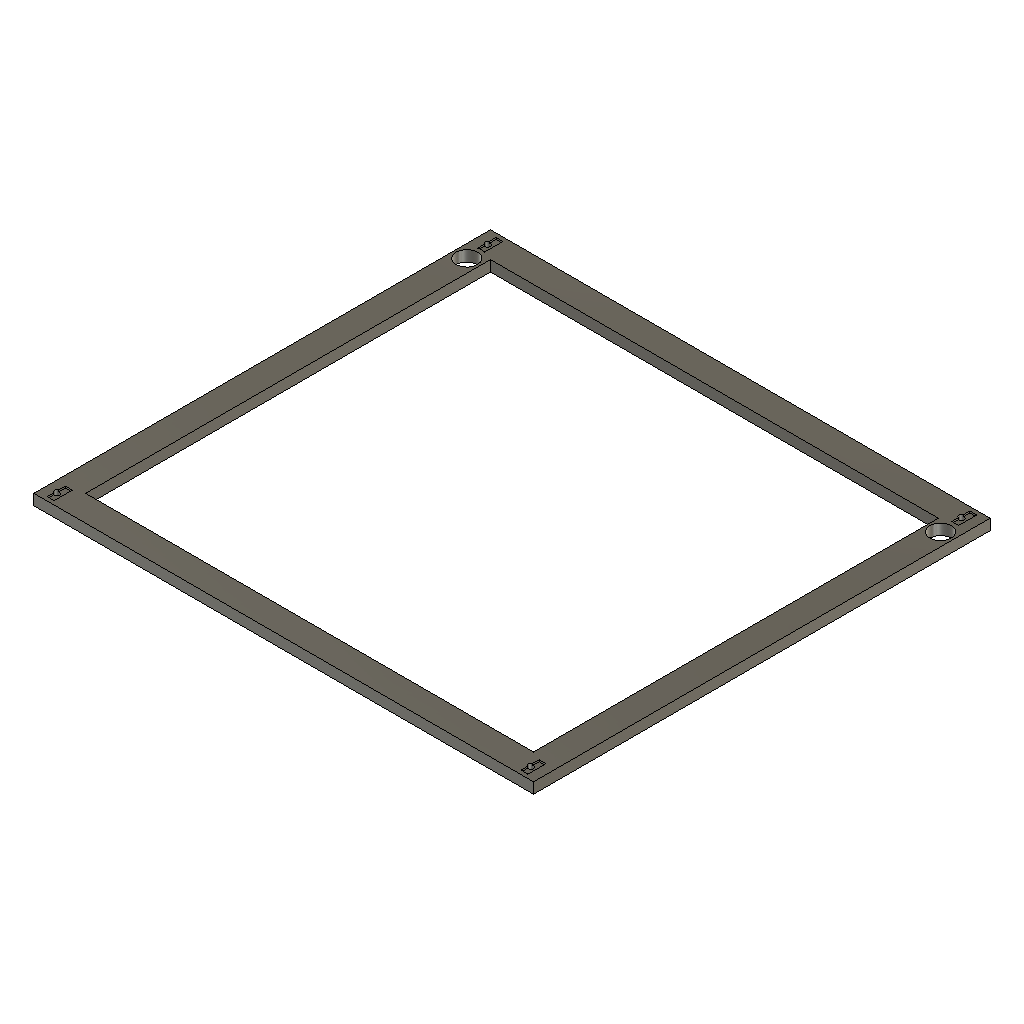
carrier-jig-240 (Autodesk Fusion 360 design; units mm, degrees)
part number: 2026-10-31-09-47-41-817
part number: 2026-10-31-09-47-42-158
Autodesk Fusion 360 part; units mm, degrees
sketch "Left spine sketch" plane through (0, 0, 0) normal (0, 0, 1) x (1, 0, 0) in component "PRINT alignment jig"
  line L0 (4, 14) -> (16, 14)
  line L1 (16, 14) -> (16, 226)
  line L2 (16, 226) -> (4, 226)
  line L3 (4, 226) -> (4, 14)
  dimension "d67" = 4
  dimension "d68" = 14
  dimension "d69" = 12
  dimension "d70" = 212
  constraint horizontal L0
  constraint vertical L1
  constraint horizontal L2
  constraint vertical L3
  measures "d67" horizontal distance of origin L0.start
  measures "d68" vertical distance of origin L0.start
  measures "d69" horizontal distance of L0.start L0.end
  measures "d70" vertical distance of L0.end L1.end
extrude "Left spine" add sketch "Left spine sketch" along normal blind 5 in component "PRINT alignment jig"
sketch "Bottom bridge sketch" plane through (0, 0, 0) normal (0, 0, 1) x (1, 0, 0) in component "PRINT alignment jig"
  line L0 (4, 14) -> (236, 14)
  line L1 (236, 14) -> (236, 26)
  line L2 (236, 26) -> (4, 26)
  line L3 (4, 26) -> (4, 14)
  dimension "d73" = 4
  dimension "d74" = 14
  dimension "d75" = 232
  dimension "d76" = 12
  constraint horizontal L0
  constraint vertical L1
  constraint horizontal L2
  constraint vertical L3
  measures "d73" horizontal distance of origin L0.start
  measures "d74" vertical distance of origin L0.start
  measures "d75" horizontal distance of L0.start L0.end
  measures "d76" vertical distance of L0.end L1.end
extrude "Bottom bridge" add sketch "Bottom bridge sketch" along normal blind 5 in component "PRINT alignment jig"
sketch "Right spine sketch" plane through (0, 0, 0) normal (0, 0, 1) x (1, 0, 0) in component "PRINT alignment jig"
  line L0 (224, 14) -> (236, 14)
  line L1 (236, 14) -> (236, 226)
  line L2 (236, 226) -> (224, 226)
  line L3 (224, 226) -> (224, 14)
  dimension "d79" = 224
  dimension "d80" = 14
  dimension "d81" = 12
  dimension "d82" = 212
  constraint horizontal L0
  constraint vertical L1
  constraint horizontal L2
  constraint vertical L3
  measures "d79" horizontal distance of origin L0.start
  measures "d80" vertical distance of origin L0.start
  measures "d81" horizontal distance of L0.start L0.end
  measures "d82" vertical distance of L0.end L1.end
extrude "Right spine" add sketch "Right spine sketch" along normal blind 5 in component "PRINT alignment jig"
sketch "Top bridge sketch" plane through (0, 0, 0) normal (0, 0, 1) x (1, 0, 0) in component "PRINT alignment jig"
  line L0 (4, 214) -> (236, 214)
  line L1 (236, 214) -> (236, 226)
  line L2 (236, 226) -> (4, 226)
  line L3 (4, 226) -> (4, 214)
  dimension "d85" = 4
  dimension "d86" = 214
  dimension "d87" = 232
  dimension "d88" = 12
  constraint horizontal L0
  constraint vertical L1
  constraint horizontal L2
  constraint vertical L3
  measures "d85" horizontal distance of origin L0.start
  measures "d86" vertical distance of origin L0.start
  measures "d87" horizontal distance of L0.start L0.end
  measures "d88" vertical distance of L0.end L1.end
extrude "Top bridge" add sketch "Top bridge sketch" along normal blind 5 in component "PRINT alignment jig"
sketch "Temporary M2 locating screw sketch" plane through (0, 0, 0) normal (0, 0, 1) x (1, 0, 0) in component "PRINT alignment jig"
  circle A0 centre (8.75, 20) radius 1.2
  dimension "d91" = 8.75
  dimension "d92" = 20
  dimension "d93" = 2.4
  measures "d91" horizontal distance of origin A0.centre
  measures "d92" vertical distance of origin A0.centre
  measures "d93" diameter of A0
extrude "Temporary M2 locating screw" cut sketch "Temporary M2 locating screw sketch" along normal blind 5 in component "PRINT alignment jig"
sketch "Flush temporary screw seat sketch" plane through (0, 0, 0) normal (0, 0, 1) x (1, 0, 0) in component "PRINT alignment jig"
  circle A0 centre (8.75, 20) radius 2
  dimension "d96" = 8.75
  dimension "d97" = 20
  dimension "d98" = 4
  measures "d96" horizontal distance of origin A0.centre
  measures "d97" vertical distance of origin A0.centre
  measures "d98" diameter of A0
extrude "Flush temporary screw seat" cut sketch "Flush temporary screw seat sketch" along normal blind 0.8 draft -45 in component "PRINT alignment jig"
ref_plane "WorkPlane1" through (0, 0, 5) normal (0, 0, 1) x (1, 0, 0) in component "PRINT alignment jig"
sketch "Carrier pad locating socket sketch" plane through (0, 0, 5) normal (0, 0, 1) x (1, 0, 0) in component "PRINT alignment jig"
  line L0 (8.4, 15.8) -> (11.6, 15.8)
  line L1 (11.6, 15.8) -> (11.6, 24.2)
  line L2 (11.6, 24.2) -> (8.4, 24.2)
  line L3 (8.4, 24.2) -> (8.4, 15.8)
  dimension "d103" = 8.4
  dimension "d104" = 15.8
  dimension "d105" = 3.2
  dimension "d106" = 8.4
  constraint horizontal L0
  constraint vertical L1
  constraint horizontal L2
  constraint vertical L3
  measures "d103" horizontal distance of origin L0.start
  measures "d104" vertical distance of origin L0.start
  measures "d105" horizontal distance of L0.start L0.end
  measures "d106" vertical distance of L0.end L1.end
extrude "Carrier pad locating socket" cut sketch "Carrier pad locating socket sketch" against normal blind 0.8 in component "PRINT alignment jig"
sketch "Temporary M2 locating screw sketch (1)" plane through (0, 0, 0) normal (0, 0, 1) x (1, 0, 0) in component "PRINT alignment jig"
  circle A0 centre (8.75, 220) radius 1.2
  dimension "d109" = 8.75
  dimension "d110" = 220
  dimension "d111" = 2.4
  measures "d109" horizontal distance of origin A0.centre
  measures "d110" vertical distance of origin A0.centre
  measures "d111" diameter of A0
extrude "Temporary M2 locating screw (1)" cut sketch "Temporary M2 locating screw sketch (1)" along normal blind 5 in component "PRINT alignment jig"
sketch "Flush temporary screw seat sketch (1)" plane through (0, 0, 0) normal (0, 0, 1) x (1, 0, 0) in component "PRINT alignment jig"
  circle A0 centre (8.75, 220) radius 2
  dimension "d114" = 8.75
  dimension "d115" = 220
  dimension "d116" = 4
  measures "d114" horizontal distance of origin A0.centre
  measures "d115" vertical distance of origin A0.centre
  measures "d116" diameter of A0
extrude "Flush temporary screw seat (1)" cut sketch "Flush temporary screw seat sketch (1)" along normal blind 0.8 draft -45 in component "PRINT alignment jig"
ref_plane "WorkPlane2" through (0, 0, 5) normal (0, 0, 1) x (1, 0, 0) in component "PRINT alignment jig"
sketch "Carrier pad locating socket sketch (1)" plane through (0, 0, 5) normal (0, 0, 1) x (1, 0, 0) in component "PRINT alignment jig"
  line L0 (8.4, 215.8) -> (11.6, 215.8)
  line L1 (11.6, 215.8) -> (11.6, 224.2)
  line L2 (11.6, 224.2) -> (8.4, 224.2)
  line L3 (8.4, 224.2) -> (8.4, 215.8)
  dimension "d121" = 8.4
  dimension "d122" = 215.8
  dimension "d123" = 3.2
  dimension "d124" = 8.4
  constraint horizontal L0
  constraint vertical L1
  constraint horizontal L2
  constraint vertical L3
  measures "d121" horizontal distance of origin L0.start
  measures "d122" vertical distance of origin L0.start
  measures "d123" horizontal distance of L0.start L0.end
  measures "d124" vertical distance of L0.end L1.end
extrude "Carrier pad locating socket (1)" cut sketch "Carrier pad locating socket sketch (1)" against normal blind 0.8 in component "PRINT alignment jig"
sketch "Upper M5 driver access sketch" plane through (0, 0, 0) normal (0, 0, 1) x (1, 0, 0) in component "PRINT alignment jig"
  circle A0 centre (10, 209) radius 5
  dimension "d127" = 10
  dimension "d128" = 209
  dimension "d129" = 10
  measures "d127" horizontal distance of origin A0.centre
  measures "d128" vertical distance of origin A0.centre
  measures "d129" diameter of A0
extrude "Upper M5 driver access" cut sketch "Upper M5 driver access sketch" along normal blind 5 in component "PRINT alignment jig"
sketch "Temporary M2 locating screw sketch (2)" plane through (0, 0, 0) normal (0, 0, 1) x (1, 0, 0) in component "PRINT alignment jig"
  circle A0 centre (228.75, 20) radius 1.2
  dimension "d132" = 228.75
  dimension "d133" = 20
  dimension "d134" = 2.4
  measures "d132" horizontal distance of origin A0.centre
  measures "d133" vertical distance of origin A0.centre
  measures "d134" diameter of A0
extrude "Temporary M2 locating screw (2)" cut sketch "Temporary M2 locating screw sketch (2)" along normal blind 5 in component "PRINT alignment jig"
sketch "Flush temporary screw seat sketch (2)" plane through (0, 0, 0) normal (0, 0, 1) x (1, 0, 0) in component "PRINT alignment jig"
  circle A0 centre (228.75, 20) radius 2
  dimension "d137" = 228.75
  dimension "d138" = 20
  dimension "d139" = 4
  measures "d137" horizontal distance of origin A0.centre
  measures "d138" vertical distance of origin A0.centre
  measures "d139" diameter of A0
extrude "Flush temporary screw seat (2)" cut sketch "Flush temporary screw seat sketch (2)" along normal blind 0.8 draft -45 in component "PRINT alignment jig"
ref_plane "WorkPlane3" through (0, 0, 5) normal (0, 0, 1) x (1, 0, 0) in component "PRINT alignment jig"
sketch "Carrier pad locating socket sketch (2)" plane through (0, 0, 5) normal (0, 0, 1) x (1, 0, 0) in component "PRINT alignment jig"
  line L0 (228.4, 15.8) -> (231.6, 15.8)
  line L1 (231.6, 15.8) -> (231.6, 24.2)
  line L2 (231.6, 24.2) -> (228.4, 24.2)
  line L3 (228.4, 24.2) -> (228.4, 15.8)
  dimension "d144" = 228.4
  dimension "d145" = 15.8
  dimension "d146" = 3.2
  dimension "d147" = 8.4
  constraint horizontal L0
  constraint vertical L1
  constraint horizontal L2
  constraint vertical L3
  measures "d144" horizontal distance of origin L0.start
  measures "d145" vertical distance of origin L0.start
  measures "d146" horizontal distance of L0.start L0.end
  measures "d147" vertical distance of L0.end L1.end
extrude "Carrier pad locating socket (2)" cut sketch "Carrier pad locating socket sketch (2)" against normal blind 0.8 in component "PRINT alignment jig"
sketch "Temporary M2 locating screw sketch (3)" plane through (0, 0, 0) normal (0, 0, 1) x (1, 0, 0) in component "PRINT alignment jig"
  circle A0 centre (228.75, 220) radius 1.2
  dimension "d150" = 228.75
  dimension "d151" = 220
  dimension "d152" = 2.4
  measures "d150" horizontal distance of origin A0.centre
  measures "d151" vertical distance of origin A0.centre
  measures "d152" diameter of A0
extrude "Temporary M2 locating screw (3)" cut sketch "Temporary M2 locating screw sketch (3)" along normal blind 5 in component "PRINT alignment jig"
sketch "Flush temporary screw seat sketch (3)" plane through (0, 0, 0) normal (0, 0, 1) x (1, 0, 0) in component "PRINT alignment jig"
  circle A0 centre (228.75, 220) radius 2
  dimension "d155" = 228.75
  dimension "d156" = 220
  dimension "d157" = 4
  measures "d155" horizontal distance of origin A0.centre
  measures "d156" vertical distance of origin A0.centre
  measures "d157" diameter of A0
extrude "Flush temporary screw seat (3)" cut sketch "Flush temporary screw seat sketch (3)" along normal blind 0.8 draft -45 in component "PRINT alignment jig"
ref_plane "WorkPlane4" through (0, 0, 5) normal (0, 0, 1) x (1, 0, 0) in component "PRINT alignment jig"
sketch "Carrier pad locating socket sketch (3)" plane through (0, 0, 5) normal (0, 0, 1) x (1, 0, 0) in component "PRINT alignment jig"
  line L0 (228.4, 215.8) -> (231.6, 215.8)
  line L1 (231.6, 215.8) -> (231.6, 224.2)
  line L2 (231.6, 224.2) -> (228.4, 224.2)
  line L3 (228.4, 224.2) -> (228.4, 215.8)
  dimension "d162" = 228.4
  dimension "d163" = 215.8
  dimension "d164" = 3.2
  dimension "d165" = 8.4
  constraint horizontal L0
  constraint vertical L1
  constraint horizontal L2
  constraint vertical L3
  measures "d162" horizontal distance of origin L0.start
  measures "d163" vertical distance of origin L0.start
  measures "d164" horizontal distance of L0.start L0.end
  measures "d165" vertical distance of L0.end L1.end
extrude "Carrier pad locating socket (3)" cut sketch "Carrier pad locating socket sketch (3)" against normal blind 0.8 in component "PRINT alignment jig"
sketch "Upper M5 driver access sketch (1)" plane through (0, 0, 0) normal (0, 0, 1) x (1, 0, 0) in component "PRINT alignment jig"
  circle A0 centre (230, 209) radius 5
  dimension "d168" = 230
  dimension "d169" = 209
  dimension "d170" = 10
  measures "d168" horizontal distance of origin A0.centre
  measures "d169" vertical distance of origin A0.centre
  measures "d170" diameter of A0
extrude "Upper M5 driver access (1)" cut sketch "Upper M5 driver access sketch (1)" along normal blind 5 in component "PRINT alignment jig"
component "PRINT alignment jig" placed x (1, 0, 0) y (0, 1, 0) z (0, 0, 1) at (0, 0, 0)
equation "columns = 12" comment "Even integer 4..14; each cell is 20 mm"
equation "rows = 12" comment "Even integer 4..14"
equation "pitch = 20 mm" comment "Keep for dense SKADIS compatible lattice"
equation "panelWidth = columns * pitch" comment "Nominal module pitch X"
equation "panelHeight = rows * pitch" comment "Nominal module pitch Y"
equation "seamGap = 0.35 mm" comment "Physical envelope shrinks around fixed lattice"
equation "boardThickness = 5 mm" comment "Fit-test with real hooks"
equation "slotWidth = 5 mm" comment "Minimum throat width"
equation "slotHeight = 15 mm" comment "Minimum throat height"
equation "entryRadius = 0.4 mm" comment "Front slot and perimeter edge rounding"
equation "cornerRadius = 6 mm" comment "Plan-view panel corner rounding"
equation "hookClearance = 10 mm" comment "PROVISIONAL unobstructed depth behind board; carriers begin at its rear boundary"
equation "frameZ = carrierZ + carrierThickness" comment "Front extrusion datum"
equation "profileMouth = 6.28 mm" comment "User measured mouth"
equation "profileCavity = 11 mm" comment "User measured widest cavity"
equation "profileDepth = 6.2 mm" comment "User measured face-to-floor depth"
equation "profileFloor = 5.7 mm" comment "User estimate, lower confidence"
equation "profileLip = 1.5 mm" comment "Unmeasured; tentative comparable catalog value"
equation "profileTaperStart = profileDepth - ( profileCavity - profileFloor ) / 2" comment "Assumed 45-degree inner slopes"
equation "profileBore = 5 mm" comment "Unmeasured central bore, reference only"
equation "nutWidth = 8.8 mm" comment "Provisional low-profile METAL T-nut envelope, not old rectangular carrier"
equation "nutLength = 12 mm" comment "End-loaded anti-rotation metal nut envelope"
equation "nutThickness = 2.7 mm" comment "Thin nut reference; fit/load still unverified"
equation "jointLeg = 18 mm" comment "In-bay angle footprint"
equation "jointThickness = 3 mm" comment "Metal bracket thickness"
equation "jointDepth = 16 mm" comment "Bracket depth within 20 mm rail"
equation "sideScrewLength = 8 mm" comment "M5x8 reference; check against actual bracket and nut"
equation "wallTabHeight = 24 mm" comment "Tab along extrusion"
equation "wallTabReach = 22 mm" comment "Tab into open bay"
equation "wallAnchorClearance = 6.5 mm" comment "Placeholder wall anchor interface"
equation "wallDriverDiameter = 12 mm" comment "Clear tool envelope in open bays"
equation "keyDriverDiameter = 5 mm" comment "Short hex-key working-leg envelope"
equation "keyDriverReach = 20 mm" comment "Short hex-key working-leg reach"
equation "supportWidth = 3.2 mm" comment "Prototype blade; two perimeter lines need print review"
equation "supportLength = 12 mm" comment "Compression bearing length"
equation "hookEnvelopeWidth = 6 mm" comment "Conservative provisional continuous hook column"
equation "carrierThickness = 7 mm" comment "Room for captive M2 nut and stock M5x12"
equation "panelClearance = 2.4 mm" comment "M2 clearance"
equation "panelHeadPocket = 4 mm" comment "DIN965 3.8 mm head plus 0.1 mm recess"
equation "carrierHeadPocket = 9.4 mm" comment "DIN965 M5 9.2 mm head plus recess"
equation "carrierBore = 5.5 mm" comment "M5 clearance"
equation "tongueWidth = 2.8 mm" comment "Rear axial registration tongue"
equation "tongueLength = 8 mm" comment "Axial release registration"
equation "tongueDepth = 0.6 mm" comment "Tongue engagement"
equation "registerClearance = 0.2 mm" comment "Each side of printed tongue"
equation "carrierZ = boardThickness + hookClearance" comment "Rear hook cavity boundary"
equation "stepCorner = 0.6 mm" comment "Small plan corner relief; printed fit remains untested"
equation "d67 = abs(4 mm)"
equation "d68 = abs(14 mm)"
equation "d70 = panelHeight - 28 mm"
equation "d71 = boardThickness"
equation "d73 = abs(4 mm)"
equation "d74 = abs(14 mm)"
equation "d75 = panelWidth - 8 mm"
equation "d77 = boardThickness"
equation "d79 = abs(panelWidth - 16 mm)"
equation "d80 = abs(14 mm)"
equation "d82 = panelHeight - 28 mm"
equation "d83 = boardThickness"
equation "d85 = abs(4 mm)"
equation "d86 = abs(panelHeight - 26 mm)"
equation "d87 = panelWidth - 8 mm"
equation "d89 = boardThickness"
equation "d91 = ( abs(pitch / 2) ) - webCenterOffset"
equation "d92 = abs(pitch)"
equation "d93 = panelClearance"
equation "d94 = boardThickness"
equation "d96 = ( abs(pitch / 2) ) - webCenterOffset"
equation "d97 = abs(pitch)"
equation "d98 = panelHeadPocket"
equation "d99 = ( panelHeadPocket - panelClearance ) / 2"
equation "d101 = boardThickness"
equation "d103 = abs(pitch / 2 - tongueWidth / 2 - registerClearance)"
equation "d104 = abs(pitch - tongueLength / 2 - registerClearance)"
equation "d105 = tongueWidth + 2 * registerClearance"
equation "d106 = tongueLength + 2 * registerClearance"
equation "d107 = -tongueDepth - 0.2 mm"
equation "d109 = ( abs(pitch / 2) ) - webCenterOffset"
equation "d110 = abs(panelHeight - pitch)"
equation "d111 = panelClearance"
equation "d112 = boardThickness"
equation "d114 = ( abs(pitch / 2) ) - webCenterOffset"
equation "d115 = abs(panelHeight - pitch)"
equation "d116 = panelHeadPocket"
equation "d117 = ( panelHeadPocket - panelClearance ) / 2"
equation "d119 = boardThickness"
equation "d121 = abs(pitch / 2 - tongueWidth / 2 - registerClearance)"
equation "d122 = abs(panelHeight - pitch - tongueLength / 2 - registerClearance)"
equation "d123 = tongueWidth + 2 * registerClearance"
equation "d124 = tongueLength + 2 * registerClearance"
equation "d125 = -tongueDepth - 0.2 mm"
equation "d127 = abs(pitch / 2)"
equation "d128 = abs(panelHeight - pitch - 11 mm)"
equation "d130 = boardThickness"
equation "d132 = ( abs(panelWidth - pitch / 2) ) - webCenterOffset"
equation "d133 = abs(pitch)"
equation "d134 = panelClearance"
equation "d135 = boardThickness"
equation "d137 = ( abs(panelWidth - pitch / 2) ) - webCenterOffset"
equation "d138 = abs(pitch)"
equation "d139 = panelHeadPocket"
equation "d140 = ( panelHeadPocket - panelClearance ) / 2"
equation "d142 = boardThickness"
equation "d144 = abs(panelWidth - pitch / 2 - tongueWidth / 2 - registerClearance)"
equation "d145 = abs(pitch - tongueLength / 2 - registerClearance)"
equation "d146 = tongueWidth + 2 * registerClearance"
equation "d147 = tongueLength + 2 * registerClearance"
equation "d148 = -tongueDepth - 0.2 mm"
equation "d150 = ( abs(panelWidth - pitch / 2) ) - webCenterOffset"
equation "d151 = abs(panelHeight - pitch)"
equation "d152 = panelClearance"
equation "d153 = boardThickness"
equation "d155 = ( abs(panelWidth - pitch / 2) ) - webCenterOffset"
equation "d156 = abs(panelHeight - pitch)"
equation "d157 = panelHeadPocket"
equation "d158 = ( panelHeadPocket - panelClearance ) / 2"
equation "d160 = boardThickness"
equation "d162 = abs(panelWidth - pitch / 2 - tongueWidth / 2 - registerClearance)"
equation "d163 = abs(panelHeight - pitch - tongueLength / 2 - registerClearance)"
equation "d164 = tongueWidth + 2 * registerClearance"
equation "d165 = tongueLength + 2 * registerClearance"
equation "d166 = -tongueDepth - 0.2 mm"
equation "d168 = abs(panelWidth - pitch / 2)"
equation "d169 = abs(panelHeight - pitch - 11 mm)"
equation "d171 = boardThickness"
equation "webCenterOffset = ( slotHeight - slotWidth ) ^ 2 / ( 4 * pitch )" comment "Match v0.6 screw axis; locating pads stay at original axis"
